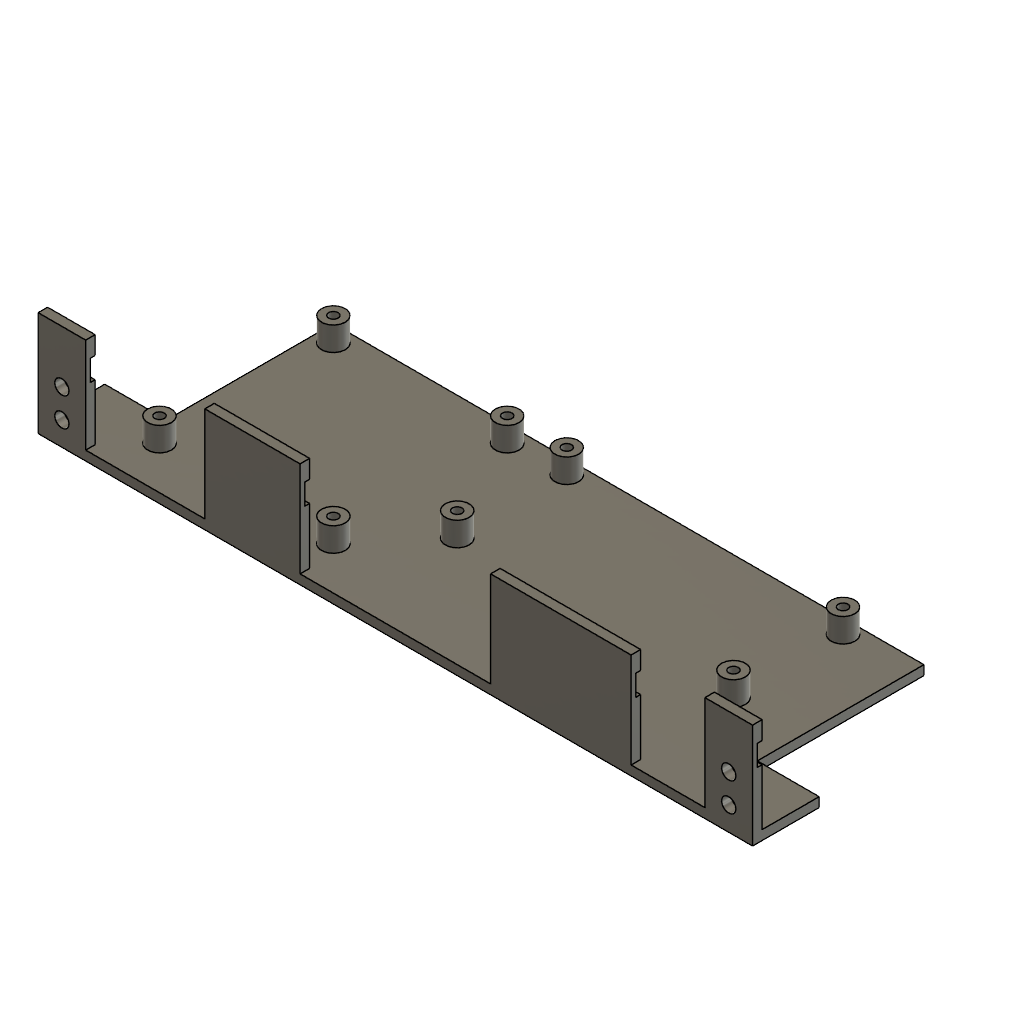
02-31_라즈베리파이패널 (Autodesk Fusion 360 design; units mm, degrees)
Autodesk Fusion 360 part; units mm, degrees
sketch "스케치1" plane through (0, 0, 0) normal (0, 1, 0) x (1, 0, 0)
  line L0 (-75, 0) -> (75, 0)
  line L1 (-75, 0) -> (-75, 14)
  line L2 (-75, 14) -> (-62, 14)
  line L3 (-62, 14) -> (-62, 49)
  line L4 (-62, 49) -> (62, 49)
  line L5 (62, 49) -> (62, 14)
  line L6 (62, 14) -> (75, 14)
  line L7 (75, 14) -> (75, 0)
  dimension "d1" = 150
  dimension "d2" = 14
  dimension "d3" = 13
  dimension "d4" = 35
  dimension "d5" = 124
  constraint horizontal L0
  constraint midpoint origin L0
  constraint perpendicular L0 L1
  constraint perpendicular L1 L2
  constraint perpendicular L0 L3
  constraint perpendicular L3 L4
  constraint perpendicular L4 L5
  constraint perpendicular L5 L6
  constraint perpendicular L0 L7
  measures "d1" distance of L0.start L0.end
  measures "d2" distance of L0.start L1.end
  measures "d3" distance of L1.end L2.end
  measures "d4" distance of L2.end L3.end
  measures "d5" distance of L3.end L4.end
extrude "돌출1" add sketch "스케치1" along normal blind 2
sketch "스케치2" plane through (0, 2, 0) normal (0, 1, 0) x (-1, 0, 0)
  line L0 (75, 0) -> (-75, 0)
  line L1 (-75, 0) -> (-75, -14)
  line L2 (-75, -14) -> (-62, -14)
  line L3 (-62, -14) -> (-62, -49)
  line L4 (-62, -49) -> (62, -49)
  line L5 (62, -49) -> (62, -14)
  line L6 (62, -14) -> (75, -14)
  line L7 (75, -14) -> (75, 0)
  line L8 (75, 0) -> (65, 0)
  line L9 (65, 0) -> (65, -2)
  line L10 (65, -2) -> (75, -2)
  line L11 (75, -2) -> (75, 0)
  line L12 (40, 0) -> (20, 0)
  line L13 (20, 0) -> (20, -2)
  line L14 (20, -2) -> (40, -2)
  line L15 (40, -2) -> (40, 0)
  line L16 (-20, 0) -> (-49.5, 0)
  line L17 (-49.5, 0) -> (-49.5, -2)
  line L18 (-49.5, -2) -> (-20, -2)
  line L19 (-20, -2) -> (-20, 0)
  line L20 (-65, 0) -> (-75, 0)
  line L21 (-75, 0) -> (-75, -2)
  line L22 (-75, -2) -> (-65, -2)
  line L23 (-65, -2) -> (-65, 0)
  dimension "d8" = 10
  dimension "d9" = 2
  dimension "d10" = 20
  dimension "d11" = 2
  dimension "d12" = 25
  dimension "d13" = 29.5
  dimension "d14" = 2
  dimension "d15" = 40
  dimension "d16" = 10
  dimension "d17" = 2
  dimension "d18" = 15.5
  constraint horizontal L8
  constraint vertical L9
  constraint horizontal L10
  constraint vertical L11
  constraint coincident L0.start L7.end
  constraint horizontal L12
  constraint vertical L13
  constraint horizontal L14
  constraint vertical L15
  constraint coincident L0 L12.start
  constraint horizontal L16
  constraint vertical L17
  constraint horizontal L18
  constraint vertical L19
  constraint coincident L0 L16.start
  constraint horizontal L20
  constraint vertical L21
  constraint horizontal L22
  constraint vertical L23
  constraint coincident L0 L20.start
  measures "d8" distance of L0.start L8.end
  measures "d9" distance of L0.start L10.end
  measures "d10" distance of L12.start L12.end
  measures "d11" distance of L12.start L14.end
  measures "d12" distance of L9 L15
  measures "d13" distance of L16.start L16.end
  measures "d14" distance of L16.start L18.end
  measures "d15" distance of L13 L19
  measures "d16" distance of L20.start L0.end
  measures "d17" distance of L20.start L22.end
  measures "d18" distance of L17 L23
extrude "돌출2" add sketch "스케치2" along normal blind 20 contours L0 L7 L8 L9 L10 L11 | L0 L12 L13 L14 L15 | L0 L16 L17 L18 L19 | L0 L1 L20 L21 L22 L23
sketch "스케치3" plane through (75, 0, 0) normal (1, 0, 0) x (0, 0, -1)
  line L0 (0, 0) -> (14, 0)
  line L1 (14, 0) -> (14, 2)
  line L2 (14, 2) -> (2, 2)
  line L3 (2, 2) -> (2, 22)
  line L4 (2, 22) -> (0, 22)
  line L5 (0, 22) -> (0, 0)
  line L6 (2, 13.8) -> (1, 13.8)
  line L7 (1, 13.8) -> (1, 18.2)
  line L8 (1, 18.2) -> (2, 18.2)
  line L9 (2, 18.2) -> (2, 13.8)
  dimension "d21" = 1
  dimension "d22" = 4.4
  dimension "d23" = 11.8
  constraint horizontal L6
  constraint vertical L7
  constraint horizontal L8
  constraint vertical L9
  constraint coincident L3 L6.start
  measures "d21" distance of L6.start L6.end
  measures "d22" distance of L6.start L8.end
  measures "d23" distance of L2 L6
extrude "돌출3" cut sketch "스케치3" against normal blind 150 contours L3 L6 L7 L8 L9
sketch "스케치4" plane through (0, 0, -2) normal (0, 0, -1) x (-1, 0, 0)
  line L0 (-65, 13.8) -> (-75, 13.8)
  line L1 (-75, 13.8) -> (-75, 2)
  line L2 (-75, 2) -> (-65, 2)
  line L3 (-65, 2) -> (-65, 13.8)
  circle A0 centre (-70, 5) radius 1.5
  circle A1 centre (-70, 11) radius 1.5
  line L4 (0, 0) -> (0, 36.3907) construction
  line L5 (75, 2) -> (65, 2)
  circle A2 centre (70, 5) radius 1.5
  line L6 (75, 13.8) -> (75, 2)
  line L7 (65, 13.8) -> (75, 13.8)
  circle A3 centre (70, 11) radius 1.5
  line L8 (65, 2) -> (65, 13.8)
  dimension "d26" = 3
  dimension "d27" = 3
  dimension "d28" = 6
  dimension "d29" = 3
  dimension "d30" = 5
  dimension "d31" = 5
  constraint coincident L4.start origin
  constraint vertical L4
  constraint symmetric L0.start L4 L7.start
  constraint symmetric L0.end L4 L6.start
  constraint symmetric L1.end L4 L5.start
  constraint symmetric L2.end L4 L5.end
  constraint symmetric A0 L4 A2
  constraint symmetric A1 L4 A3
  measures "d26" diameter of A0
  measures "d27" diameter of A1
  measures "d28" distance of A0.centre A1.centre
  measures "d29" distance of L2 A0.centre
  measures "d30" distance of L1 A0.centre
  measures "d31" distance of L1 A1.centre
extrude "돌출4" cut sketch "스케치4" against normal blind 2 contours A0 | A1 | A2 | A3
sketch "스케치5" plane through (0, 2, 0) normal (0, 1, 0) x (-1, 0, 0)
  line L0 (-65, 0) -> (-65, -2)
  line L1 (-65, -2) -> (-75, -2)
  line L2 (-75, -2) -> (-75, -14)
  line L3 (-75, -14) -> (-62, -14)
  line L4 (-62, -14) -> (-62, -49)
  line L5 (-62, -49) -> (62, -49)
  line L6 (62, -49) -> (62, -14)
  line L7 (62, -14) -> (75, -14)
  line L8 (75, -14) -> (75, -2)
  line L9 (75, -2) -> (65, -2)
  line L10 (65, -2) -> (65, 0)
  line L11 (65, 0) -> (40, 0)
  line L12 (40, 0) -> (40, -2)
  line L13 (40, -2) -> (20, -2)
  line L14 (20, -2) -> (20, 0)
  line L15 (20, 0) -> (-20, 0)
  line L16 (-20, 0) -> (-20, -2)
  line L17 (-20, -2) -> (-49.5, -2)
  line L18 (-49.5, -2) -> (-49.5, 0)
  line L19 (-49.5, 0) -> (-65, 0)
  line L20 (10, -46) -> (-48, -46) construction
  line L21 (-48, -46) -> (-48, -23) construction
  line L22 (-48, -23) -> (10, -23) construction
  line L23 (10, -23) -> (10, -46) construction
  circle A0 centre (10, -46) radius 2.5
  circle A1 centre (10, -46) radius 1
  circle A2 centre (-48, -46) radius 2.5
  circle A3 centre (-48, -46) radius 1
  circle A4 centre (-48, -23) radius 2.5
  circle A5 centre (-48, -23) radius 1
  circle A6 centre (10, -23) radius 2.5
  circle A7 centre (10, -23) radius 1
  dimension "d34" = 58
  dimension "d35" = 23
  dimension "d36" = 10
  dimension "d37" = 23
  dimension "d38" = 5
  dimension "d39" = 2
  dimension "d40" = 5
  dimension "d41" = 2
  dimension "d42" = 5
  dimension "d43" = 2
  dimension "d44" = 5
  dimension "d45" = 2
  constraint horizontal L20
  constraint vertical L21
  constraint horizontal L22
  constraint vertical L23
  constraint coincident L20.start L23.end
  constraint concentric A0 A1
  constraint coincident L20.end L21.start
  constraint concentric A2 A3
  constraint coincident L21.end L22.start
  constraint concentric A4 A5
  constraint coincident L22.end L23.start
  constraint concentric A6 A7
  measures "d34" distance of L20.start L20.end
  measures "d35" distance of L20.start L22.end
  measures "d36" distance of origin L23
  measures "d37" distance of L19 L22
  measures "d38" diameter of A0
  measures "d39" diameter of A1
  measures "d40" diameter of A2
  measures "d41" diameter of A3
  measures "d42" diameter of A4
  measures "d43" diameter of A5
  measures "d44" diameter of A6
  measures "d45" diameter of A7
extrude "돌출5" add sketch "스케치5" along normal blind 5 contours A0 | A2 | A4 | A6
sketch "스케치6" plane through (0, 2, 0) normal (0, 1, 0) x (-1, 0, 0)
  circle A0 centre (10, -46) radius 2.5
  circle A1 centre (10, -23) radius 2.5
  line L0 (-65, 0) -> (-65, -2)
  line L1 (-65, -2) -> (-75, -2)
  line L2 (-75, -2) -> (-75, -14)
  line L3 (-75, -14) -> (-62, -14)
  line L4 (-62, -14) -> (-62, -49)
  line L5 (-62, -49) -> (62, -49)
  line L6 (62, -49) -> (62, -14)
  line L7 (62, -14) -> (75, -14)
  line L8 (75, -14) -> (75, -2)
  line L9 (75, -2) -> (65, -2)
  line L10 (65, -2) -> (65, 0)
  line L11 (65, 0) -> (40, 0)
  line L12 (40, 0) -> (40, -2)
  line L13 (40, -2) -> (20, -2)
  line L14 (20, -2) -> (20, 0)
  line L15 (20, 0) -> (-20, 0)
  line L16 (-20, 0) -> (-20, -2)
  line L17 (-20, -2) -> (-49.5, -2)
  line L18 (-49.5, -2) -> (-49.5, 0)
  line L19 (-49.5, 0) -> (-65, 0)
  circle A2 centre (-48, -23) radius 2.5
  circle A3 centre (-48, -46) radius 2.5
  line L20 (58.5, -45.5) -> (22, -45.5) construction
  line L21 (22, -45.5) -> (22, -9) construction
  line L22 (22, -9) -> (58.5, -9) construction
  line L23 (58.5, -9) -> (58.5, -45.5) construction
  circle A4 centre (58.5, -45.5) radius 2.5
  circle A5 centre (58.5, -45.5) radius 1
  circle A6 centre (22, -45.5) radius 2.5
  circle A7 centre (22, -45.5) radius 1
  circle A8 centre (22, -9) radius 2.5
  circle A9 centre (22, -9) radius 1
  circle A10 centre (58.5, -9) radius 2.5
  circle A11 centre (58.5, -9) radius 1
  dimension "d48" = 36.5
  dimension "d49" = 36.5
  dimension "d50" = 9
  dimension "d51" = 22
  dimension "d52" = 5
  dimension "d53" = 2
  dimension "d54" = 5
  dimension "d55" = 2
  dimension "d56" = 5
  dimension "d57" = 2
  dimension "d58" = 5
  dimension "d59" = 2
  constraint horizontal L20
  constraint vertical L21
  constraint horizontal L22
  constraint vertical L23
  constraint coincident L20.start L23.end
  constraint concentric A4 A5
  constraint coincident L20.end L21.start
  constraint concentric A6 A7
  constraint coincident L21.end L22.start
  constraint concentric A8 A9
  constraint coincident L22.end L23.start
  constraint concentric A10 A11
  measures "d48" distance of L20.start L20.end
  measures "d49" distance of L20.start L22.end
  measures "d50" distance of L11 L22
  measures "d51" distance of origin L21
  measures "d52" diameter of A4
  measures "d53" diameter of A5
  measures "d54" diameter of A6
  measures "d55" diameter of A7
  measures "d56" diameter of A8
  measures "d57" diameter of A9
  measures "d58" diameter of A10
  measures "d59" diameter of A11
extrude "돌출6" add sketch "스케치6" along normal blind 5 contours A4 | A6 | A8 | A10
equation "d49 = d48"
